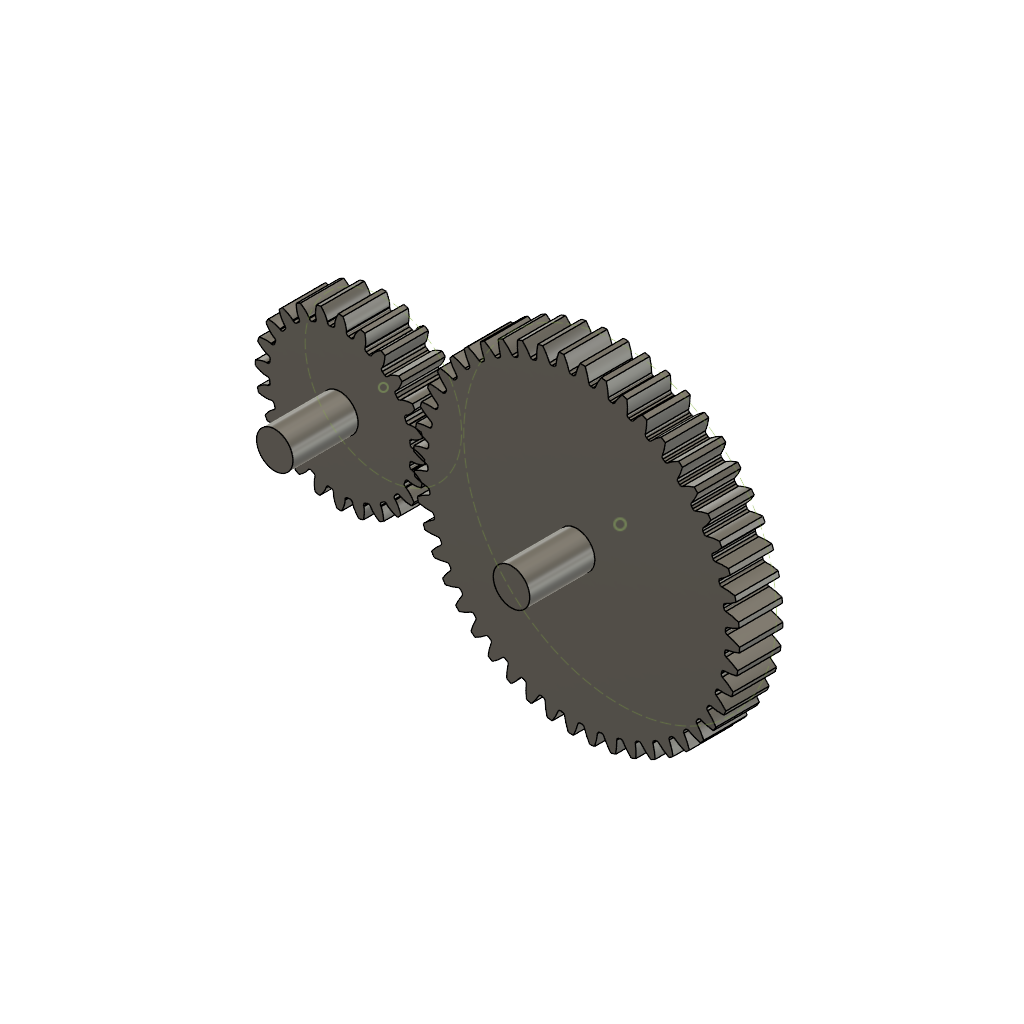
spur gear working (Autodesk Fusion 360 design; units mm, degrees)
part number: 2026-09-27-16-30-44-236
description: Spur Gear; Module: 1.5; Num Teeth: 24; Pressure Angle: 20.0; Backlash: 0.00 mm
part number: 2026-09-27-16-31-31-578
description: Spur Gear; Module: 1.5; Num Teeth: 48; Pressure Angle: 20.0; Backlash: 0.00 mm
part number: 2026-09-27-16-31-54-748
part number: 2026-09-27-16-35-08-701
part number: 2026-09-27-16-35-54-532
Autodesk Fusion 360 part; units mm, degrees
(part 1 of 7)
sketch "Base Circle" plane through (0, 0, 0) normal (0, 0, 1) x (1, 0, 0) in component "Spur Gear 24 teeth"
  circle A0 centre (0, 0) radius 16.2645
  circle A1 centre (0, 0) radius 4.2
extrude "Extrude1" add sketch "Base Circle" along normal blind 10 makes body 1 in component "Spur Gear 24 teeth"
sketch "Gear Tooth" plane through (0, 0, 0) normal (0, 0, 1) x (1, 0, 0) in component "Spur Gear 24 teeth"
  spline S0 degree 5 poles (16.8599, -1.3577) (16.8674, -1.3583) (16.8825, -1.3593) (16.9052, -1.3603) (16.9354, -1.3605) (16.9732, -1.3593) (17.0111, -1.357) (17.049, -1.3541) (17.0869, -1.3508) (17.1248, -1.3472) (17.1628, -1.3434) (17.2007, -1.3393) (17.2387, -1.3347) (17.2766, -1.3297) (17.3146, -1.3241) (17.3526, -1.318) (17.3906, -1.3115) (17.4285, -1.3047) (17.4665, -1.2975) (17.5045, -1.2901) (17.5425, -1.2824) (17.5804, -1.2744) (17.6184, -1.2661) (17.6563, -1.2574) (17.6943, -1.2485) (17.7322, -1.2392) (17.7701, -1.2297) (17.808, -1.2198) (17.8459, -1.2097) (17.8838, -1.1994) (17.9217, -1.1888) (17.9596, -1.1779) (17.9974, -1.1667) (18.0352, -1.1553) (18.0731, -1.1437) (18.1109, -1.1318) (18.1486, -1.1196) (18.1864, -1.1072) (18.2242, -1.0946) (18.2619, -1.0817) (18.2996, -1.0686) (18.3373, -1.0553) (18.3749, -1.0417) (18.4126, -1.0279) (18.4502, -1.0139) (18.4878, -0.9996) (18.5254, -0.9852) (18.563, -0.9705) (18.6005, -0.9556) (18.638, -0.9404) (18.6755, -0.9251) (18.7129, -0.9096) (18.7504, -0.8938) (18.7878, -0.8778) (18.8251, -0.8617) (18.8625, -0.8453) (18.8998, -0.8287) (18.9371, -0.8119) (18.9743, -0.7949) (19.0116, -0.7777) (19.0488, -0.7604) (19.0859, -0.7428) (19.1231, -0.725) (19.1602, -0.707) (19.1973, -0.6888) (19.2343, -0.6705) (19.2713, -0.6519) (19.3083, -0.6332) (19.3452, -0.6143) (19.3821, -0.5951) (19.419, -0.5758) (19.4485, -0.5602) (19.4705, -0.5484) (19.4853, -0.5406) (19.4926, -0.5366) knots 0 0 0 0 0 0 0.01428571 0.02857143 0.04285714 0.05714286 0.07142857 0.08571429 0.1 0.11428571 0.12857143 0.14285714 0.15714286 0.17142857 0.18571429 0.2 0.21428571 0.22857143 0.24285714 0.25714286 0.27142857 0.28571429 0.3 0.31428571 0.32857143 0.34285714 0.35714286 0.37142857 0.38571429 0.4 0.41428571 0.42857143 0.44285714 0.45714286 0.47142857 0.48571429 0.5 0.51428571 0.52857143 0.54285714 0.55714286 0.57142857 0.58571429 0.6 0.61428571 0.62857143 0.64285714 0.65714286 0.67142857 0.68571429 0.7 0.71428571 0.72857143 0.74285714 0.75714286 0.77142857 0.78571429 0.8 0.81428571 0.82857143 0.84285714 0.85714286 0.87142857 0.88571429 0.9 0.91428571 0.92857143 0.94285714 0.95714286 0.97142857 0.98571429 1 1 1 1 1 1
  spline S1 degree 5 poles (16.8599, 1.3577) (16.8674, 1.3583) (16.8825, 1.3593) (16.9052, 1.3603) (16.9354, 1.3605) (16.9732, 1.3593) (17.0111, 1.357) (17.049, 1.3541) (17.0869, 1.3508) (17.1248, 1.3472) (17.1628, 1.3434) (17.2007, 1.3393) (17.2387, 1.3347) (17.2766, 1.3297) (17.3146, 1.3241) (17.3526, 1.318) (17.3906, 1.3115) (17.4285, 1.3047) (17.4665, 1.2975) (17.5045, 1.2901) (17.5425, 1.2824) (17.5804, 1.2744) (17.6184, 1.2661) (17.6563, 1.2574) (17.6943, 1.2485) (17.7322, 1.2392) (17.7701, 1.2297) (17.808, 1.2198) (17.8459, 1.2097) (17.8838, 1.1994) (17.9217, 1.1888) (17.9596, 1.1779) (17.9974, 1.1667) (18.0352, 1.1553) (18.0731, 1.1437) (18.1109, 1.1318) (18.1486, 1.1196) (18.1864, 1.1072) (18.2242, 1.0946) (18.2619, 1.0817) (18.2996, 1.0686) (18.3373, 1.0553) (18.3749, 1.0417) (18.4126, 1.0279) (18.4502, 1.0139) (18.4878, 0.9996) (18.5254, 0.9852) (18.563, 0.9705) (18.6005, 0.9556) (18.638, 0.9404) (18.6755, 0.9251) (18.7129, 0.9096) (18.7504, 0.8938) (18.7878, 0.8778) (18.8251, 0.8617) (18.8625, 0.8453) (18.8998, 0.8287) (18.9371, 0.8119) (18.9743, 0.7949) (19.0116, 0.7777) (19.0488, 0.7604) (19.0859, 0.7428) (19.1231, 0.725) (19.1602, 0.707) (19.1973, 0.6888) (19.2343, 0.6705) (19.2713, 0.6519) (19.3083, 0.6332) (19.3452, 0.6143) (19.3821, 0.5951) (19.419, 0.5758) (19.4485, 0.5602) (19.4705, 0.5484) (19.4853, 0.5406) (19.4926, 0.5366) knots 0 0 0 0 0 0 0.01428571 0.02857143 0.04285714 0.05714286 0.07142857 0.08571429 0.1 0.11428571 0.12857143 0.14285714 0.15714286 0.17142857 0.18571429 0.2 0.21428571 0.22857143 0.24285714 0.25714286 0.27142857 0.28571429 0.3 0.31428571 0.32857143 0.34285714 0.35714286 0.37142857 0.38571429 0.4 0.41428571 0.42857143 0.44285714 0.45714286 0.47142857 0.48571429 0.5 0.51428571 0.52857143 0.54285714 0.55714286 0.57142857 0.58571429 0.6 0.61428571 0.62857143 0.64285714 0.65714286 0.67142857 0.68571429 0.7 0.71428571 0.72857143 0.74285714 0.75714286 0.77142857 0.78571429 0.8 0.81428571 0.82857143 0.84285714 0.85714286 0.87142857 0.88571429 0.9 0.91428571 0.92857143 0.94285714 0.95714286 0.97142857 0.98571429 1 1 1 1 1 1
  arc A0 (19.4926, -0.5366) -> (19.4926, 0.5366) centre (0, 0) ccw
  line L0 (16.2021, -1.3047) -> (16.8599, -1.3577)
  line L1 (16.2021, 1.3047) -> (16.8599, 1.3577)
  line L2 (16.2021, -1.3047) -> (16.2021, 1.3047)
  point P0 (17.0454, -1.3543)
  point P1 (17.2322, -1.3354)
  point P2 (17.4196, -1.3062)
  point P3 (17.6076, -1.2684)
  point P4 (17.7959, -1.2229)
  point P5 (17.9845, -1.1705)
  point P6 (18.1733, -1.1115)
  point P7 (18.3621, -1.0463)
  point P8 (18.551, -0.9751)
  point P9 (18.7398, -0.8982)
  point P10 (18.9284, -0.8158)
  point P11 (19.1168, -0.728)
  point P12 (19.3049, -0.6349)
  point P13 (17.0454, 1.3543)
  point P14 (17.2322, 1.3354)
  point P15 (17.4196, 1.3062)
  point P16 (17.6076, 1.2684)
  point P17 (17.7959, 1.2229)
  point P18 (17.9845, 1.1705)
  point P19 (18.1733, 1.1115)
  point P20 (18.3621, 1.0463)
  point P21 (18.551, 0.9751)
  point P22 (18.7398, 0.8982)
  point P23 (18.9284, 0.8158)
  point P24 (19.1168, 0.728)
  point P25 (19.3049, 0.6349)
extrude "Extrude2" add sketch "Gear Tooth" along normal blind 10 bodies 1 in component "Spur Gear 24 teeth"
fillet "Fillet1" radius 0.5 2 edges at (16.212, -1.3055, 5) (16.212, 1.3055, 5) on bodies 1 in component "Spur Gear 24 teeth"
pattern_circular "C-Pattern1" count 24 over 360 about axis through (0, 0, 0) along (0, 0, 1) of "Extrude2", "Fillet1" in component "Spur Gear 24 teeth"
sketch "Diametrial Pitch Circle" plane through (0, 0, 0) normal (0, 0, 1) x (1, 0, 0) in component "Spur Gear 24 teeth"
  circle A0 centre (0, 0) radius 18 construction
sketch "Base Circle (2)" plane through (0, 0, 0) normal (0, 0, 1) x (1, 0, 0) in component "Spur Gear 48 teeth"
  circle A0 centre (0, 0) radius 34.2645
  circle A1 centre (0, 0) radius 4.2
extrude "Extrude1'" add sketch "Base Circle (2)" along normal blind 10 separate body makes body 2 in component "Spur Gear 48 teeth"
sketch "Gear Tooth (2)" plane through (0, 0, 0) normal (0, 0, 1) x (1, 0, 0) in component "Spur Gear 48 teeth"
  spline S0 degree 5 poles (33.7906, -1.6106) (33.8012, -1.6107) (33.8226, -1.6107) (33.8546, -1.6104) (33.8974, -1.6095) (33.9508, -1.6076) (34.0042, -1.6048) (34.0576, -1.6012) (34.1111, -1.5968) (34.1645, -1.5917) (34.218, -1.5859) (34.2714, -1.5796) (34.3249, -1.5727) (34.3783, -1.5654) (34.4318, -1.5577) (34.4852, -1.5495) (34.5386, -1.541) (34.592, -1.532) (34.6454, -1.5226) (34.6988, -1.5128) (34.7521, -1.5026) (34.8055, -1.4921) (34.8588, -1.4812) (34.9121, -1.4699) (34.9654, -1.4583) (35.0187, -1.4464) (35.072, -1.4341) (35.1252, -1.4215) (35.1785, -1.4086) (35.2317, -1.3954) (35.2849, -1.3819) (35.338, -1.3681) (35.3912, -1.3539) (35.4443, -1.3395) (35.4974, -1.3248) (35.5505, -1.3098) (35.6036, -1.2945) (35.6566, -1.279) (35.7096, -1.2632) (35.7626, -1.2471) (35.8156, -1.2307) (35.8686, -1.2141) (35.9215, -1.1972) (35.9744, -1.18) (36.0272, -1.1626) (36.0801, -1.145) (36.1329, -1.1271) (36.1857, -1.1089) (36.2385, -1.0905) (36.2912, -1.0718) (36.3439, -1.0529) (36.3966, -1.0338) (36.4492, -1.0144) (36.5018, -0.9948) (36.5544, -0.975) (36.607, -0.9549) (36.6595, -0.9346) (36.712, -0.9141) (36.7645, -0.8933) (36.8169, -0.8723) (36.8693, -0.8511) (36.9217, -0.8297) (36.974, -0.808) (37.0263, -0.7862) (37.0786, -0.7641) (37.1308, -0.7418) (37.183, -0.7193) (37.2352, -0.6965) (37.2873, -0.6736) (37.3394, -0.6504) (37.3915, -0.6271) (37.4331, -0.6082) (37.4643, -0.594) (37.4851, -0.5844) (37.4955, -0.5797) knots 0 0 0 0 0 0 0.01428571 0.02857143 0.04285714 0.05714286 0.07142857 0.08571429 0.1 0.11428571 0.12857143 0.14285714 0.15714286 0.17142857 0.18571429 0.2 0.21428571 0.22857143 0.24285714 0.25714286 0.27142857 0.28571429 0.3 0.31428571 0.32857143 0.34285714 0.35714286 0.37142857 0.38571429 0.4 0.41428571 0.42857143 0.44285714 0.45714286 0.47142857 0.48571429 0.5 0.51428571 0.52857143 0.54285714 0.55714286 0.57142857 0.58571429 0.6 0.61428571 0.62857143 0.64285714 0.65714286 0.67142857 0.68571429 0.7 0.71428571 0.72857143 0.74285714 0.75714286 0.77142857 0.78571429 0.8 0.81428571 0.82857143 0.84285714 0.85714286 0.87142857 0.88571429 0.9 0.91428571 0.92857143 0.94285714 0.95714286 0.97142857 0.98571429 1 1 1 1 1 1
  spline S1 degree 5 poles (33.7906, 1.6106) (33.8012, 1.6107) (33.8226, 1.6107) (33.8546, 1.6104) (33.8974, 1.6095) (33.9508, 1.6076) (34.0042, 1.6048) (34.0576, 1.6012) (34.1111, 1.5968) (34.1645, 1.5917) (34.218, 1.5859) (34.2714, 1.5796) (34.3249, 1.5727) (34.3783, 1.5654) (34.4318, 1.5577) (34.4852, 1.5495) (34.5386, 1.541) (34.592, 1.532) (34.6454, 1.5226) (34.6988, 1.5128) (34.7521, 1.5026) (34.8055, 1.4921) (34.8588, 1.4812) (34.9121, 1.4699) (34.9654, 1.4583) (35.0187, 1.4464) (35.072, 1.4341) (35.1252, 1.4215) (35.1785, 1.4086) (35.2317, 1.3954) (35.2849, 1.3819) (35.338, 1.3681) (35.3912, 1.3539) (35.4443, 1.3395) (35.4974, 1.3248) (35.5505, 1.3098) (35.6036, 1.2945) (35.6566, 1.279) (35.7096, 1.2632) (35.7626, 1.2471) (35.8156, 1.2307) (35.8686, 1.2141) (35.9215, 1.1972) (35.9744, 1.18) (36.0272, 1.1626) (36.0801, 1.145) (36.1329, 1.1271) (36.1857, 1.1089) (36.2385, 1.0905) (36.2912, 1.0718) (36.3439, 1.0529) (36.3966, 1.0338) (36.4492, 1.0144) (36.5018, 0.9948) (36.5544, 0.975) (36.607, 0.9549) (36.6595, 0.9346) (36.712, 0.9141) (36.7645, 0.8933) (36.8169, 0.8723) (36.8693, 0.8511) (36.9217, 0.8297) (36.974, 0.808) (37.0263, 0.7862) (37.0786, 0.7641) (37.1308, 0.7418) (37.183, 0.7193) (37.2352, 0.6965) (37.2873, 0.6736) (37.3394, 0.6504) (37.3915, 0.6271) (37.4331, 0.6082) (37.4643, 0.594) (37.4851, 0.5844) (37.4955, 0.5797) knots 0 0 0 0 0 0 0.01428571 0.02857143 0.04285714 0.05714286 0.07142857 0.08571429 0.1 0.11428571 0.12857143 0.14285714 0.15714286 0.17142857 0.18571429 0.2 0.21428571 0.22857143 0.24285714 0.25714286 0.27142857 0.28571429 0.3 0.31428571 0.32857143 0.34285714 0.35714286 0.37142857 0.38571429 0.4 0.41428571 0.42857143 0.44285714 0.45714286 0.47142857 0.48571429 0.5 0.51428571 0.52857143 0.54285714 0.55714286 0.57142857 0.58571429 0.6 0.61428571 0.62857143 0.64285714 0.65714286 0.67142857 0.68571429 0.7 0.71428571 0.72857143 0.74285714 0.75714286 0.77142857 0.78571429 0.8 0.81428571 0.82857143 0.84285714 0.85714286 0.87142857 0.88571429 0.9 0.91428571 0.92857143 0.94285714 0.95714286 0.97142857 0.98571429 1 1 1 1 1 1
  arc A0 (37.4955, -0.5797) -> (37.4955, 0.5797) centre (0, 0) ccw
  line L0 (33.7906, 1.6106) -> (33.7906, -1.6106)
  point P0 (34.0535, -1.6013)
  point P1 (34.3173, -1.5736)
  point P2 (34.5816, -1.5337)
  point P3 (34.8462, -1.4837)
  point P4 (35.1111, -1.4248)
  point P5 (35.3762, -1.3579)
  point P6 (35.6414, -1.2834)
  point P7 (35.9066, -1.2019)
  point P8 (36.1718, -1.1136)
  point P9 (36.4369, -1.0189)
  point P10 (36.7019, -0.918)
  point P11 (36.9667, -0.811)
  point P12 (37.2312, -0.6982)
  point P13 (34.0535, 1.6013)
  point P14 (34.3173, 1.5736)
  point P15 (34.5816, 1.5337)
  point P16 (34.8462, 1.4837)
  point P17 (35.1111, 1.4248)
  point P18 (35.3762, 1.3579)
  point P19 (35.6414, 1.2834)
  point P20 (35.9066, 1.2019)
  point P21 (36.1718, 1.1136)
  point P22 (36.4369, 1.0189)
  point P23 (36.7019, 0.918)
  point P24 (36.9667, 0.811)
  point P25 (37.2312, 0.6982)
extrude "Extrude2'" add sketch "Gear Tooth (2)" along normal blind 10 bodies 2 in component "Spur Gear 48 teeth"
fillet "Fillet1'" radius 0.5 2 edges at (34.2278, 1.5846, 5) (34.2278, -1.5846, 5) on bodies 2 in component "Spur Gear 48 teeth"
pattern_circular "C-Pattern1'" count 48 over 360 about axis through (0, 0, 0) along (0, 0, 1) of "Extrude2'", "Fillet1'" in component "Spur Gear 48 teeth"
sketch "Diametrial Pitch Circle (2)" plane through (0, 0, 0) normal (0, 0, 1) x (1, 0, 0) in component "Spur Gear 48 teeth"
  circle A0 centre (0, 0) radius 36 construction
sketch "Sketch1" plane through (0, 0, 10) normal (0, 0, 1) x (1, 0, 0)
  arc A0 (88.7647, -0.2836) -> (88.7647, 0.2182) centre (54.5011, -0.0327) ccw
  spline S0 degree 3 poles (89.146, 0.7076) (89.0828, 0.6922) (89.0231, 0.6645) (88.9178, 0.5879) (88.8732, 0.5397) (88.8145, 0.4445) (88.7957, 0.4015) (88.7705, 0.3115) (88.7643, 0.2649) (88.7647, 0.2182) knots 0 0 0 0 0.019532 0.019532 0.039064 0.039064 0.053081 0.053081 0.067098 0.067098 0.067098 0.067098
  spline S1 degree 5 poles (89.146, 0.7076) (89.1512, 0.7089) (89.1669, 0.7127) (89.1931, 0.7192) (89.2298, 0.7285) (89.2771, 0.7408) (89.3296, 0.7548) (89.3821, 0.7692) (89.4346, 0.7839) (89.487, 0.799) (89.5394, 0.8144) (89.5918, 0.8301) (89.6441, 0.8461) (89.6963, 0.8625) (89.7486, 0.8791) (89.8008, 0.8961) (89.8529, 0.9134) (89.905, 0.931) (89.9571, 0.9488) (90.0091, 0.967) (90.0611, 0.9854) (90.1131, 1.0041) (90.165, 1.0231) (90.2169, 1.0424) (90.2687, 1.0619) (90.3205, 1.0817) (90.3722, 1.1017) (90.4239, 1.1221) (90.4756, 1.1426) (90.5272, 1.1635) (90.5788, 1.1845) (90.6303, 1.2059) (90.6818, 1.2274) (90.7333, 1.2493) (90.7847, 1.2713) (90.836, 1.2936) (90.8873, 1.3162) (90.9386, 1.3389) (90.9898, 1.3619) (91.041, 1.3852) (91.0921, 1.4086) (91.1432, 1.4323) (91.1943, 1.4563) (91.2452, 1.4804) (91.2962, 1.5048) (91.3471, 1.5294) (91.398, 1.5542) (91.4488, 1.5792) (91.4995, 1.6044) (91.5502, 1.6299) (91.6009, 1.6556) (91.6515, 1.6815) (91.7021, 1.7076) (91.7526, 1.7339) (91.8031, 1.7604) (91.8535, 1.7871) (91.8938, 1.8086) (91.924, 1.8249) (91.9442, 1.8357) (91.9542, 1.8412) knots 0.221564 0.221564 0.221564 0.221564 0.221564 0.221564 0.228571 0.242857 0.257143 0.271429 0.285714 0.3 0.314286 0.328571 0.342857 0.357143 0.371429 0.385714 0.4 0.414286 0.428571 0.442857 0.457143 0.471429 0.485714 0.5 0.514286 0.528571 0.542857 0.557143 0.571429 0.585714 0.6 0.614286 0.628571 0.642857 0.657143 0.671429 0.685714 0.7 0.714286 0.728571 0.742857 0.757143 0.771429 0.785714 0.8 0.814286 0.828571 0.842857 0.857143 0.871429 0.885714 0.9 0.914286 0.928571 0.942857 0.957143 0.971429 0.985714 1 1 1 1 1 1
  arc A1 (91.9542, 1.8412) -> (91.8784, 2.9981) centre (54.5011, -0.0327) ccw
  spline S2 degree 5 poles (91.8784, 2.9981) (91.8677, 3.0021) (91.8463, 3.0103) (91.8143, 3.0225) (91.7715, 3.0386) (91.718, 3.0585) (91.6645, 3.0782) (91.611, 3.0976) (91.5574, 3.1169) (91.5039, 3.136) (91.4503, 3.1548) (91.3967, 3.1734) (91.3431, 3.1918) (91.2894, 3.21) (91.2358, 3.228) (91.1821, 3.2457) (91.1284, 3.2632) (91.0747, 3.2805) (91.021, 3.2976) (90.9672, 3.3144) (90.9135, 3.331) (90.8597, 3.3473) (90.8059, 3.3635) (90.7521, 3.3793) (90.6983, 3.395) (90.6445, 3.4104) (90.5906, 3.4256) (90.5368, 3.4405) (90.4829, 3.4551) (90.429, 3.4696) (90.3751, 3.4837) (90.3212, 3.4976) (90.2673, 3.5113) (90.2134, 3.5247) (90.1595, 3.5378) (90.1056, 3.5507) (90.0516, 3.5633) (89.9977, 3.5756) (89.9438, 3.5877) (89.8898, 3.5994) (89.8359, 3.6109) (89.7819, 3.6221) (89.7279, 3.633) (89.674, 3.6436) (89.62, 3.654) (89.566, 3.664) (89.5121, 3.6737) (89.4581, 3.6831) (89.4042, 3.6922) (89.3502, 3.7009) (89.2963, 3.7093) (89.2423, 3.7174) (89.1884, 3.7252) (89.1344, 3.7326) (89.0805, 3.7396) (89.0321, 3.7456) (88.9945, 3.75) (88.9676, 3.7531) (88.9515, 3.7548) (88.9463, 3.7554) knots -1 -1 -1 -1 -1 -1 -0.985714 -0.971429 -0.957143 -0.942857 -0.928571 -0.914286 -0.9 -0.885714 -0.871429 -0.857143 -0.842857 -0.828571 -0.814286 -0.8 -0.785714 -0.771429 -0.757143 -0.742857 -0.728571 -0.714286 -0.7 -0.685714 -0.671429 -0.657143 -0.642857 -0.628571 -0.614286 -0.6 -0.585714 -0.571429 -0.557143 -0.542857 -0.528571 -0.514286 -0.5 -0.485714 -0.471429 -0.457143 -0.442857 -0.428571 -0.414286 -0.4 -0.385714 -0.371429 -0.357143 -0.342857 -0.328571 -0.314286 -0.3 -0.285714 -0.271429 -0.257143 -0.242857 -0.228571 -0.221564 -0.221564 -0.221564 -0.221564 -0.221564 -0.221564
  spline S3 degree 3 poles (88.5043, 4.1908) (88.5123, 4.1262) (88.5329, 4.0638) (88.5968, 3.9503) (88.6395, 3.9004) (88.7273, 3.8311) (88.7678, 3.8074) (88.8543, 3.772) (88.8998, 3.7605) (88.9463, 3.7554) knots 0 0 0 0 0.019532 0.019532 0.039064 0.039064 0.053081 0.053081 0.067098 0.067098 0.067098 0.067098
  arc A2 (88.5043, 4.1908) -> (88.4388, 4.6884) centre (54.5011, -0.0327) ccw
  spline S4 degree 3 poles (88.753, 5.2233) (88.6923, 5.1998) (88.6368, 5.1646) (88.5424, 5.0749) (88.5044, 5.0212) (88.4587, 4.9192) (88.4456, 4.8741) (88.4324, 4.7816) (88.4323, 4.7346) (88.4388, 4.6884) knots 0 0 0 0 0.019532 0.019532 0.039064 0.039064 0.053081 0.053081 0.067098 0.067098 0.067098 0.067098
  spline S5 degree 5 poles (88.753, 5.2233) (88.758, 5.2253) (88.773, 5.2311) (88.7982, 5.241) (88.8334, 5.255) (88.8786, 5.2733) (88.9289, 5.2941) (88.979, 5.3152) (89.0291, 5.3367) (89.0791, 5.3584) (89.1291, 5.3805) (89.1789, 5.4029) (89.2287, 5.4257) (89.2784, 5.4487) (89.328, 5.4721) (89.3775, 5.4957) (89.427, 5.5196) (89.4764, 5.5439) (89.5257, 5.5684) (89.5749, 5.5932) (89.624, 5.6182) (89.6731, 5.6435) (89.7221, 5.6691) (89.771, 5.695) (89.8198, 5.7211) (89.8686, 5.7475) (89.9173, 5.7742) (89.9659, 5.8011) (90.0144, 5.8282) (90.0629, 5.8556) (90.1113, 5.8832) (90.1596, 5.9111) (90.2078, 5.9392) (90.256, 5.9675) (90.304, 5.9961) (90.352, 6.0249) (90.4, 6.054) (90.4478, 6.0832) (90.4956, 6.1127) (90.5433, 6.1425) (90.5909, 6.1724) (90.6385, 6.2026) (90.686, 6.2329) (90.7334, 6.2635) (90.7807, 6.2943) (90.828, 6.3254) (90.8752, 6.3566) (90.9223, 6.3881) (90.9693, 6.4197) (91.0163, 6.4516) (91.0632, 6.4836) (91.11, 6.5159) (91.1567, 6.5484) (91.2034, 6.581) (91.2499, 6.6139) (91.2964, 6.647) (91.3336, 6.6736) (91.3614, 6.6937) (91.3799, 6.7071) (91.3892, 6.7138) knots 0.221564 0.221564 0.221564 0.221564 0.221564 0.221564 0.228571 0.242857 0.257143 0.271429 0.285714 0.3 0.314286 0.328571 0.342857 0.357143 0.371429 0.385714 0.4 0.414286 0.428571 0.442857 0.457143 0.471429 0.485714 0.5 0.514286 0.528571 0.542857 0.557143 0.571429 0.585714 0.6 0.614286 0.628571 0.642857 0.657143 0.671429 0.685714 0.7 0.714286 0.728571 0.742857 0.757143 0.771429 0.785714 0.8 0.814286 0.828571 0.842857 0.857143 0.871429 0.885714 0.9 0.914286 0.928571 0.942857 0.957143 0.971429 0.985714 1 1 1 1 1 1
  arc A3 (91.3892, 6.7138) -> (91.163, 7.8508) centre (54.5011, -0.0327) ccw
  spline S6 degree 5 poles (91.163, 7.8508) (91.1519, 7.8535) (91.1297, 7.8588) (91.0963, 7.8667) (91.0518, 7.877) (90.9961, 7.8898) (90.9405, 7.9023) (90.8849, 7.9147) (90.8293, 7.9268) (90.7737, 7.9387) (90.7181, 7.9504) (90.6626, 7.9618) (90.607, 7.9731) (90.5514, 7.9841) (90.4959, 7.9949) (90.4404, 8.0055) (90.3848, 8.0158) (90.3293, 8.026) (90.2738, 8.0359) (90.2184, 8.0455) (90.1629, 8.055) (90.1074, 8.0642) (90.052, 8.0731) (89.9966, 8.0819) (89.9412, 8.0903) (89.8858, 8.0986) (89.8305, 8.1066) (89.7751, 8.1144) (89.7198, 8.1219) (89.6645, 8.1291) (89.6092, 8.1361) (89.554, 8.1429) (89.4988, 8.1494) (89.4436, 8.1557) (89.3884, 8.1616) (89.3333, 8.1673) (89.2781, 8.1728) (89.223, 8.178) (89.168, 8.1829) (89.113, 8.1875) (89.058, 8.1919) (89.003, 8.1959) (88.9481, 8.1997) (88.8932, 8.2032) (88.8384, 8.2064) (88.7835, 8.2093) (88.7288, 8.2118) (88.6741, 8.2141) (88.6194, 8.2161) (88.5647, 8.2177) (88.5101, 8.219) (88.4556, 8.22) (88.4011, 8.2206) (88.3467, 8.2209) (88.2923, 8.2209) (88.2435, 8.2205) (88.2056, 8.22) (88.1786, 8.2195) (88.1624, 8.2191) (88.1571, 8.219) knots -1 -1 -1 -1 -1 -1 -0.985714 -0.971429 -0.957143 -0.942857 -0.928571 -0.914286 -0.9 -0.885714 -0.871429 -0.857143 -0.842857 -0.828571 -0.814286 -0.8 -0.785714 -0.771429 -0.757143 -0.742857 -0.728571 -0.714286 -0.7 -0.685714 -0.671429 -0.657143 -0.642857 -0.628571 -0.614286 -0.6 -0.585714 -0.571429 -0.557143 -0.542857 -0.528571 -0.514286 -0.5 -0.485714 -0.471429 -0.457143 -0.442857 -0.428571 -0.414286 -0.4 -0.385714 -0.371429 -0.357143 -0.342857 -0.328571 -0.314286 -0.3 -0.285714 -0.271429 -0.257143 -0.242857 -0.228571 -0.221564 -0.221564 -0.221564 -0.221564 -0.221564 -0.221564
  spline S7 degree 3 poles (87.6621, 8.593) (87.6785, 8.53) (87.707, 8.4708) (87.7852, 8.3666) (87.8341, 8.3227) (87.9301, 8.2654) (87.9734, 8.2473) (88.0638, 8.2235) (88.1104, 8.218) (88.1571, 8.219) knots 0 0 0 0 0.019532 0.019532 0.039064 0.039064 0.053081 0.053081 0.067098 0.067098 0.067098 0.067098
  arc A4 (87.6621, 8.593) -> (87.5322, 9.0777) centre (54.5011, -0.0327) ccw
  spline S8 degree 3 poles (87.7739, 9.6492) (87.7168, 9.6179) (87.6664, 9.5757) (87.5845, 9.4745) (87.5538, 9.4163) (87.5218, 9.3092) (87.5147, 9.2628) (87.5137, 9.1693) (87.5198, 9.1228) (87.5322, 9.0777) knots 0 0 0 0 0.019532 0.019532 0.039064 0.039064 0.053081 0.053081 0.067098 0.067098 0.067098 0.067098
  spline S9 degree 5 poles (87.7739, 9.6492) (87.7786, 9.6517) (87.7927, 9.6595) (87.8164, 9.6726) (87.8495, 9.691) (87.8919, 9.7151) (87.939, 9.7422) (87.986, 9.7697) (88.0329, 9.7975) (88.0796, 9.8257) (88.1263, 9.8541) (88.1728, 9.8828) (88.2191, 9.9118) (88.2654, 9.9412) (88.3115, 9.9708) (88.3576, 10.0007) (88.4035, 10.0309) (88.4493, 10.0613) (88.4949, 10.0921) (88.5405, 10.1231) (88.586, 10.1543) (88.6313, 10.1859) (88.6765, 10.2176) (88.7216, 10.2497) (88.7666, 10.2819) (88.8115, 10.3145) (88.8563, 10.3472) (88.901, 10.3802) (88.9456, 10.4135) (88.9901, 10.447) (89.0344, 10.4807) (89.0787, 10.5146) (89.1228, 10.5488) (89.1669, 10.5832) (89.2108, 10.6178) (89.2547, 10.6526) (89.2984, 10.6876) (89.342, 10.7229) (89.3855, 10.7584) (89.429, 10.7941) (89.4723, 10.83) (89.5155, 10.8661) (89.5586, 10.9024) (89.6016, 10.9389) (89.6445, 10.9757) (89.6873, 11.0126) (89.73, 11.0497) (89.7726, 11.087) (89.8151, 11.1246) (89.8575, 11.1623) (89.8998, 11.2002) (89.942, 11.2383) (89.9841, 11.2766) (90.0261, 11.3151) (90.068, 11.3537) (90.1098, 11.3926) (90.1431, 11.4238) (90.1681, 11.4474) (90.1847, 11.4631) (90.193, 11.4709) knots 0.221564 0.221564 0.221564 0.221564 0.221564 0.221564 0.228571 0.242857 0.257143 0.271429 0.285714 0.3 0.314286 0.328571 0.342857 0.357143 0.371429 0.385714 0.4 0.414286 0.428571 0.442857 0.457143 0.471429 0.485714 0.5 0.514286 0.528571 0.542857 0.557143 0.571429 0.585714 0.6 0.614286 0.628571 0.642857 0.657143 0.671429 0.685714 0.7 0.714286 0.728571 0.742857 0.757143 0.771429 0.785714 0.8 0.814286 0.828571 0.842857 0.857143 0.871429 0.885714 0.9 0.914286 0.928571 0.942857 0.957143 0.971429 0.985714 1 1 1 1 1 1
  arc A5 (90.193, 11.4709) -> (89.8204, 12.5687) centre (54.5011, -0.0327) ccw
  spline S10 degree 5 poles (89.8204, 12.5687) (89.809, 12.5699) (89.7862, 12.5723) (89.7521, 12.5757) (89.7066, 12.5802) (89.6498, 12.5856) (89.5931, 12.5908) (89.5363, 12.5957) (89.4796, 12.6005) (89.4229, 12.605) (89.3663, 12.6094) (89.3097, 12.6135) (89.2531, 12.6174) (89.1966, 12.621) (89.1401, 12.6245) (89.0837, 12.6277) (89.0273, 12.6308) (88.971, 12.6336) (88.9146, 12.6361) (88.8584, 12.6385) (88.8022, 12.6406) (88.746, 12.6425) (88.6898, 12.6441) (88.6338, 12.6455) (88.5777, 12.6467) (88.5218, 12.6477) (88.4658, 12.6484) (88.4099, 12.6488) (88.3541, 12.6491) (88.2984, 12.6491) (88.2426, 12.6488) (88.187, 12.6483) (88.1314, 12.6475) (88.0758, 12.6465) (88.0204, 12.6452) (87.9649, 12.6437) (87.9096, 12.6419) (87.8543, 12.6399) (87.7991, 12.6375) (87.7439, 12.6349) (87.6888, 12.6321) (87.6338, 12.6289) (87.5789, 12.6255) (87.524, 12.6218) (87.4692, 12.6178) (87.4145, 12.6135) (87.3598, 12.6089) (87.3053, 12.604) (87.2508, 12.5988) (87.1964, 12.5933) (87.1421, 12.5875) (87.0879, 12.5813) (87.0338, 12.5749) (86.9798, 12.5681) (86.9259, 12.5609) (86.8776, 12.5542) (86.8401, 12.5487) (86.8134, 12.5447) (86.7974, 12.5422) (86.7921, 12.5414) knots -1 -1 -1 -1 -1 -1 -0.985714 -0.971429 -0.957143 -0.942857 -0.928571 -0.914286 -0.9 -0.885714 -0.871429 -0.857143 -0.842857 -0.828571 -0.814286 -0.8 -0.785714 -0.771429 -0.757143 -0.742857 -0.728571 -0.714286 -0.7 -0.685714 -0.671429 -0.657143 -0.642857 -0.628571 -0.614286 -0.6 -0.585714 -0.571429 -0.557143 -0.542857 -0.528571 -0.514286 -0.5 -0.485714 -0.471429 -0.457143 -0.442857 -0.428571 -0.414286 -0.4 -0.385714 -0.371429 -0.357143 -0.342857 -0.328571 -0.314286 -0.3 -0.285714 -0.271429 -0.257143 -0.242857 -0.228571 -0.221564 -0.221564 -0.221564 -0.221564 -0.221564 -0.221564
  spline S11 degree 3 poles (86.2525, 12.8476) (86.277, 12.7873) (86.313, 12.7323) (86.4041, 12.6392) (86.4583, 12.6021) (86.561, 12.5578) (86.6063, 12.5455) (86.699, 12.5336) (86.746, 12.5343) (86.7921, 12.5414) knots 0 0 0 0 0.019532 0.019532 0.039064 0.039064 0.053081 0.053081 0.067098 0.067098 0.067098 0.067098
  arc A6 (86.2525, 12.8476) -> (86.0605, 13.3112) centre (54.5011, -0.0327) ccw
  spline S12 degree 3 poles (86.2255, 13.9093) (86.173, 13.8708) (86.1285, 13.8225) (86.0605, 13.7114) (86.0377, 13.6497) (86.0199, 13.5393) (86.019, 13.4924) (86.0302, 13.3996) (86.0423, 13.3543) (86.0605, 13.3112) knots 0 0 0 0 0.019532 0.019532 0.039064 0.039064 0.053081 0.053081 0.067098 0.067098 0.067098 0.067098
  spline S13 degree 5 poles (86.2255, 13.9093) (86.2298, 13.9124) (86.2428, 13.922) (86.2646, 13.938) (86.295, 13.9607) (86.3339, 13.9901) (86.3771, 14.0232) (86.4201, 14.0565) (86.4629, 14.0902) (86.5056, 14.1242) (86.5481, 14.1585) (86.5905, 14.193) (86.6327, 14.2279) (86.6747, 14.263) (86.7166, 14.2984) (86.7583, 14.334) (86.7999, 14.3699) (86.8413, 14.4061) (86.8826, 14.4426) (86.9237, 14.4792) (86.9647, 14.5162) (87.0055, 14.5533) (87.0462, 14.5907) (87.0868, 14.6284) (87.1272, 14.6662) (87.1674, 14.7044) (87.2076, 14.7427) (87.2476, 14.7812) (87.2874, 14.82) (87.3271, 14.859) (87.3667, 14.8982) (87.4062, 14.9376) (87.4455, 14.9773) (87.4847, 15.0171) (87.5237, 15.0572) (87.5626, 15.0974) (87.6014, 15.1379) (87.64, 15.1786) (87.6786, 15.2194) (87.717, 15.2605) (87.7552, 15.3017) (87.7933, 15.3432) (87.8314, 15.3848) (87.8692, 15.4266) (87.907, 15.4686) (87.9446, 15.5108) (87.9821, 15.5532) (88.0194, 15.5958) (88.0567, 15.6385) (88.0938, 15.6815) (88.1308, 15.7246) (88.1676, 15.7678) (88.2044, 15.8113) (88.241, 15.8549) (88.2775, 15.8987) (88.3138, 15.9427) (88.3428, 15.9781) (88.3645, 16.0046) (88.379, 16.0224) (88.3862, 16.0313) knots 0.221564 0.221564 0.221564 0.221564 0.221564 0.221564 0.228571 0.242857 0.257143 0.271429 0.285714 0.3 0.314286 0.328571 0.342857 0.357143 0.371429 0.385714 0.4 0.414286 0.428571 0.442857 0.457143 0.471429 0.485714 0.5 0.514286 0.528571 0.542857 0.557143 0.571429 0.585714 0.6 0.614286 0.628571 0.642857 0.657143 0.671429 0.685714 0.7 0.714286 0.728571 0.742857 0.757143 0.771429 0.785714 0.8 0.814286 0.828571 0.842857 0.857143 0.871429 0.885714 0.9 0.914286 0.928571 0.942857 0.957143 0.971429 0.985714 1 1 1 1 1 1
  arc A7 (88.3862, 16.0313) -> (87.8734, 17.071) centre (54.5011, -0.0327) ccw
  spline S14 degree 5 poles (87.8734, 17.071) (87.862, 17.0707) (87.8391, 17.0701) (87.8048, 17.069) (87.7591, 17.0675) (87.7021, 17.0655) (87.6451, 17.0632) (87.5882, 17.0607) (87.5314, 17.058) (87.4746, 17.0551) (87.4179, 17.052) (87.3612, 17.0487) (87.3047, 17.0452) (87.2481, 17.0415) (87.1917, 17.0375) (87.1353, 17.0334) (87.079, 17.029) (87.0228, 17.0244) (86.9666, 17.0196) (86.9105, 17.0146) (86.8545, 17.0093) (86.7986, 17.0039) (86.7427, 16.9982) (86.6869, 16.9923) (86.6312, 16.9861) (86.5756, 16.9798) (86.52, 16.9732) (86.4646, 16.9664) (86.4092, 16.9593) (86.3539, 16.952) (86.2987, 16.9445) (86.2436, 16.9367) (86.1886, 16.9287) (86.1336, 16.9204) (86.0788, 16.9119) (86.024, 16.9032) (85.9694, 16.8942) (85.9148, 16.8849) (85.8604, 16.8754) (85.806, 16.8656) (85.7518, 16.8556) (85.6977, 16.8453) (85.6436, 16.8347) (85.5897, 16.8239) (85.5359, 16.8128) (85.4822, 16.8014) (85.4287, 16.7897) (85.3752, 16.7777) (85.3219, 16.7655) (85.2687, 16.7529) (85.2156, 16.74) (85.1627, 16.7269) (85.1099, 16.7134) (85.0572, 16.6996) (85.0047, 16.6854) (84.9577, 16.6725) (84.9212, 16.6621) (84.8953, 16.6547) (84.8797, 16.6501) (84.8746, 16.6487) knots -1 -1 -1 -1 -1 -1 -0.985714 -0.971429 -0.957143 -0.942857 -0.928571 -0.914286 -0.9 -0.885714 -0.871429 -0.857143 -0.842857 -0.828571 -0.814286 -0.8 -0.785714 -0.771429 -0.757143 -0.742857 -0.728571 -0.714286 -0.7 -0.685714 -0.671429 -0.657143 -0.642857 -0.628571 -0.614286 -0.6 -0.585714 -0.571429 -0.557143 -0.542857 -0.528571 -0.514286 -0.5 -0.485714 -0.471429 -0.457143 -0.442857 -0.428571 -0.414286 -0.4 -0.385714 -0.371429 -0.357143 -0.342857 -0.328571 -0.314286 -0.3 -0.285714 -0.271429 -0.257143 -0.242857 -0.228571 -0.221564 -0.221564 -0.221564 -0.221564 -0.221564 -0.221564
  spline S15 degree 3 poles (84.2997, 16.8818) (84.3318, 16.8252) (84.3747, 16.7754) (84.4772, 16.695) (84.5357, 16.6652) (84.6433, 16.6348) (84.6899, 16.6284) (84.7833, 16.6288) (84.8298, 16.6356) (84.8746, 16.6487) knots 0 0 0 0 0.019532 0.019532 0.039064 0.039064 0.053081 0.053081 0.067098 0.067098 0.067098 0.067098
  arc A8 (84.2997, 16.8818) -> (84.0487, 17.3164) centre (54.5011, -0.0327) ccw
  spline S16 degree 3 poles (84.1343, 17.9309) (84.0873, 17.8859) (84.0495, 17.8321) (83.9966, 17.7131) (83.982, 17.6491) (83.9788, 17.5373) (83.984, 17.4906) (84.0072, 17.4001) (84.0251, 17.3567) (84.0487, 17.3164) knots 0 0 0 0 0.019532 0.019532 0.039064 0.039064 0.053081 0.053081 0.067098 0.067098 0.067098 0.067098
  spline S17 degree 5 poles (84.1343, 17.9309) (84.1382, 17.9346) (84.1498, 17.9458) (84.1693, 17.9645) (84.1965, 17.9909) (84.2312, 18.0251) (84.2697, 18.0636) (84.308, 18.1023) (84.3461, 18.1413) (84.384, 18.1805) (84.4216, 18.22) (84.4591, 18.2598) (84.4964, 18.2999) (84.5335, 18.3402) (84.5704, 18.3807) (84.6071, 18.4215) (84.6436, 18.4626) (84.68, 18.5038) (84.7161, 18.5453) (84.7521, 18.5871) (84.7879, 18.629) (84.8236, 18.6712) (84.859, 18.7136) (84.8943, 18.7562) (84.9295, 18.7991) (84.9644, 18.8421) (84.9992, 18.8853) (85.0338, 18.9288) (85.0683, 18.9724) (85.1025, 19.0163) (85.1367, 19.0603) (85.1706, 19.1046) (85.2044, 19.149) (85.2381, 19.1936) (85.2716, 19.2384) (85.3049, 19.2834) (85.3381, 19.3286) (85.3711, 19.3739) (85.4039, 19.4195) (85.4366, 19.4652) (85.4692, 19.5111) (85.5016, 19.5571) (85.5338, 19.6034) (85.5659, 19.6498) (85.5978, 19.6964) (85.6296, 19.7431) (85.6613, 19.79) (85.6928, 19.8371) (85.7241, 19.8843) (85.7553, 19.9317) (85.7863, 19.9793) (85.8172, 20.027) (85.848, 20.0749) (85.8786, 20.123) (85.909, 20.1712) (85.9394, 20.2195) (85.9635, 20.2583) (85.9815, 20.2875) (85.9935, 20.307) (85.9995, 20.3167) knots 0.221564 0.221564 0.221564 0.221564 0.221564 0.221564 0.228571 0.242857 0.257143 0.271429 0.285714 0.3 0.314286 0.328571 0.342857 0.357143 0.371429 0.385714 0.4 0.414286 0.428571 0.442857 0.457143 0.471429 0.485714 0.5 0.514286 0.528571 0.542857 0.557143 0.571429 0.585714 0.6 0.614286 0.628571 0.642857 0.657143 0.671429 0.685714 0.7 0.714286 0.728571 0.742857 0.757143 0.771429 0.785714 0.8 0.814286 0.828571 0.842857 0.857143 0.871429 0.885714 0.9 0.914286 0.928571 0.942857 0.957143 0.971429 0.985714 1 1 1 1 1 1
  arc A9 (85.9995, 20.3167) -> (85.3554, 21.2807) centre (54.5011, -0.0327) ccw
  spline S18 degree 5 poles (85.3554, 21.2807) (85.3441, 21.2789) (85.3215, 21.2752) (85.2877, 21.2697) (85.2426, 21.2623) (85.1863, 21.2528) (85.1301, 21.2431) (85.074, 21.2332) (85.018, 21.2231) (84.9621, 21.2129) (84.9063, 21.2024) (84.8506, 21.1917) (84.7949, 21.1808) (84.7394, 21.1697) (84.6839, 21.1585) (84.6286, 21.147) (84.5733, 21.1353) (84.5182, 21.1234) (84.4631, 21.1113) (84.4081, 21.099) (84.3533, 21.0865) (84.2985, 21.0738) (84.2439, 21.0609) (84.1894, 21.0477) (84.1349, 21.0344) (84.0806, 21.0208) (84.0264, 21.007) (83.9723, 20.993) (83.9183, 20.9788) (83.8645, 20.9643) (83.8107, 20.9496) (83.7571, 20.9347) (83.7036, 20.9196) (83.6502, 20.9043) (83.5969, 20.8887) (83.5438, 20.8729) (83.4908, 20.8568) (83.4379, 20.8405) (83.3852, 20.824) (83.3326, 20.8072) (83.2801, 20.7902) (83.2278, 20.7729) (83.1756, 20.7553) (83.1235, 20.7376) (83.0716, 20.7195) (83.0199, 20.7012) (82.9683, 20.6826) (82.9169, 20.6638) (82.8656, 20.6447) (82.8145, 20.6253) (82.7636, 20.6056) (82.7128, 20.5856) (82.6622, 20.5654) (82.6118, 20.5448) (82.5616, 20.5239) (82.5167, 20.5049) (82.4819, 20.4899) (82.4571, 20.4791) (82.4423, 20.4726) (82.4374, 20.4705) knots -1 -1 -1 -1 -1 -1 -0.985714 -0.971429 -0.957143 -0.942857 -0.928571 -0.914286 -0.9 -0.885714 -0.871429 -0.857143 -0.842857 -0.828571 -0.814286 -0.8 -0.785714 -0.771429 -0.757143 -0.742857 -0.728571 -0.714286 -0.7 -0.685714 -0.671429 -0.657143 -0.642857 -0.628571 -0.614286 -0.6 -0.585714 -0.571429 -0.557143 -0.542857 -0.528571 -0.514286 -0.5 -0.485714 -0.471429 -0.457143 -0.442857 -0.428571 -0.414286 -0.4 -0.385714 -0.371429 -0.357143 -0.342857 -0.328571 -0.314286 -0.3 -0.285714 -0.271429 -0.257143 -0.242857 -0.228571 -0.221564 -0.221564 -0.221564 -0.221564 -0.221564 -0.221564
  spline S19 degree 3 poles (81.8369, 20.6266) (81.8762, 20.5746) (81.9252, 20.5309) (82.0373, 20.4646) (82.0993, 20.4427) (82.2099, 20.4265) (82.2569, 20.4263) (82.3495, 20.4389) (82.3947, 20.4516) (82.4374, 20.4705) knots 0 0 0 0 0.019532 0.019532 0.039064 0.039064 0.053081 0.053081 0.067098 0.067098 0.067098 0.067098
  arc A10 (81.8369, 20.6266) -> (81.5314, 21.0247) centre (54.5011, -0.0327) ccw
  spline S20 degree 3 poles (81.5361, 21.6451) (81.4953, 21.5944) (81.4648, 21.5361) (81.4279, 21.4113) (81.4219, 21.3458) (81.4332, 21.2346) (81.4445, 21.189) (81.4793, 21.1023) (81.5027, 21.0616) (81.5314, 21.0247) knots 0 0 0 0 0.019532 0.019532 0.039064 0.039064 0.053081 0.053081 0.067098 0.067098 0.067098 0.067098
  spline S21 degree 5 poles (81.5361, 21.6451) (81.5394, 21.6493) (81.5495, 21.6619) (81.5664, 21.683) (81.5899, 21.7127) (81.6199, 21.7512) (81.653, 21.7943) (81.6859, 21.8377) (81.7186, 21.8813) (81.751, 21.9252) (81.7832, 21.9693) (81.8152, 22.0136) (81.8469, 22.0582) (81.8784, 22.103) (81.9097, 22.148) (81.9408, 22.1933) (81.9716, 22.2387) (82.0023, 22.2844) (82.0327, 22.3303) (82.063, 22.3763) (82.093, 22.4226) (82.1228, 22.4691) (82.1524, 22.5158) (82.1819, 22.5626) (82.2111, 22.6097) (82.2401, 22.6569) (82.269, 22.7043) (82.2976, 22.7519) (82.3261, 22.7997) (82.3544, 22.8476) (82.3824, 22.8957) (82.4103, 22.944) (82.4381, 22.9925) (82.4656, 23.0411) (82.4929, 23.0899) (82.5201, 23.1388) (82.5471, 23.188) (82.5739, 23.2372) (82.6005, 23.2867) (82.627, 23.3363) (82.6533, 23.386) (82.6794, 23.4359) (82.7053, 23.486) (82.7311, 23.5362) (82.7567, 23.5865) (82.7821, 23.637) (82.8073, 23.6877) (82.8324, 23.7384) (82.8573, 23.7894) (82.882, 23.8404) (82.9066, 23.8917) (82.931, 23.943) (82.9552, 23.9945) (82.9793, 24.0461) (83.0032, 24.0979) (83.027, 24.1498) (83.0458, 24.1914) (83.0599, 24.2227) (83.0692, 24.2435) (83.0739, 24.254) knots 0.221564 0.221564 0.221564 0.221564 0.221564 0.221564 0.228571 0.242857 0.257143 0.271429 0.285714 0.3 0.314286 0.328571 0.342857 0.357143 0.371429 0.385714 0.4 0.414286 0.428571 0.442857 0.457143 0.471429 0.485714 0.5 0.514286 0.528571 0.542857 0.557143 0.571429 0.585714 0.6 0.614286 0.628571 0.642857 0.657143 0.671429 0.685714 0.7 0.714286 0.728571 0.742857 0.757143 0.771429 0.785714 0.8 0.814286 0.828571 0.842857 0.857143 0.871429 0.885714 0.9 0.914286 0.928571 0.942857 0.957143 0.971429 0.985714 1 1 1 1 1 1
  arc A11 (83.0739, 24.254) -> (82.3095, 25.1256) centre (54.5011, -0.0327) ccw
  spline S22 degree 5 poles (82.3095, 25.1256) (82.2985, 25.1224) (82.2766, 25.1158) (82.2438, 25.106) (82.2, 25.0927) (82.1455, 25.0759) (82.091, 25.059) (82.0367, 25.0419) (81.9825, 25.0245) (81.9284, 25.0071) (81.8744, 24.9894) (81.8206, 24.9715) (81.7668, 24.9535) (81.7132, 24.9352) (81.6597, 24.9168) (81.6063, 24.8982) (81.5531, 24.8794) (81.4999, 24.8604) (81.4469, 24.8413) (81.394, 24.8219) (81.3413, 24.8023) (81.2887, 24.7826) (81.2362, 24.7626) (81.1838, 24.7425) (81.1316, 24.7221) (81.0795, 24.7016) (81.0276, 24.6808) (80.9758, 24.6599) (80.9241, 24.6387) (80.8726, 24.6174) (80.8212, 24.5958) (80.77, 24.574) (80.7189, 24.5521) (80.668, 24.5299) (80.6172, 24.5075) (80.5666, 24.4848) (80.5161, 24.462) (80.4658, 24.4389) (80.4157, 24.4157) (80.3657, 24.3922) (80.3159, 24.3684) (80.2663, 24.3445) (80.2169, 24.3203) (80.1676, 24.2958) (80.1185, 24.2712) (80.0696, 24.2463) (80.0209, 24.2211) (79.9723, 24.1957) (79.924, 24.1701) (79.8759, 24.1442) (79.8279, 24.118) (79.7802, 24.0916) (79.7327, 24.0649) (79.6854, 24.0379) (79.6383, 24.0107) (79.5963, 23.986) (79.5637, 23.9666) (79.5406, 23.9526) (79.5268, 23.9443) (79.5222, 23.9415) knots -1 -1 -1 -1 -1 -1 -0.985714 -0.971429 -0.957143 -0.942857 -0.928571 -0.914286 -0.9 -0.885714 -0.871429 -0.857143 -0.842857 -0.828571 -0.814286 -0.8 -0.785714 -0.771429 -0.757143 -0.742857 -0.728571 -0.714286 -0.7 -0.685714 -0.671429 -0.657143 -0.642857 -0.628571 -0.614286 -0.6 -0.585714 -0.571429 -0.557143 -0.542857 -0.528571 -0.514286 -0.5 -0.485714 -0.471429 -0.457143 -0.442857 -0.428571 -0.414286 -0.4 -0.385714 -0.371429 -0.357143 -0.342857 -0.328571 -0.314286 -0.3 -0.285714 -0.271429 -0.257143 -0.242857 -0.228571 -0.221564 -0.221564 -0.221564 -0.221564 -0.221564 -0.221564
  spline S23 degree 3 poles (78.9065, 24.0179) (78.9522, 23.9715) (79.0065, 23.9345) (79.1263, 23.8834) (79.1906, 23.8698) (79.3024, 23.8682) (79.349, 23.8741) (79.4392, 23.8987) (79.4823, 23.9172) (79.5222, 23.9415) knots 0 0 0 0 0.019532 0.019532 0.039064 0.039064 0.053081 0.053081 0.067098 0.067098 0.067098 0.067098
  arc A12 (78.9065, 24.0179) -> (78.5517, 24.3727) centre (54.5011, -0.0327) ccw
  spline S24 degree 3 poles (78.4753, 24.9885) (78.4415, 24.9328) (78.4189, 24.8711) (78.3986, 24.7425) (78.4011, 24.6768) (78.4269, 24.568) (78.444, 24.5243) (78.4899, 24.4428) (78.5184, 24.4055) (78.5517, 24.3727) knots 0 0 0 0 0.019532 0.019532 0.039064 0.039064 0.053081 0.053081 0.067098 0.067098 0.067098 0.067098
  spline S25 degree 5 poles (78.4753, 24.9885) (78.478, 24.993) (78.4864, 25.0068) (78.5004, 25.03) (78.5198, 25.0625) (78.5445, 25.1046) (78.5717, 25.1516) (78.5987, 25.1989) (78.6254, 25.2464) (78.6518, 25.2942) (78.678, 25.3421) (78.7039, 25.3902) (78.7295, 25.4386) (78.7549, 25.4871) (78.7801, 25.5358) (78.805, 25.5847) (78.8296, 25.6338) (78.854, 25.6831) (78.8782, 25.7326) (78.9022, 25.7822) (78.9259, 25.832) (78.9494, 25.8819) (78.9727, 25.9321) (78.9958, 25.9824) (79.0186, 26.0328) (79.0412, 26.0834) (79.0636, 26.1342) (79.0858, 26.1851) (79.1078, 26.2362) (79.1296, 26.2874) (79.1512, 26.3388) (79.1725, 26.3903) (79.1937, 26.442) (79.2146, 26.4938) (79.2354, 26.5457) (79.2559, 26.5978) (79.2763, 26.65) (79.2964, 26.7024) (79.3164, 26.7549) (79.3361, 26.8075) (79.3557, 26.8603) (79.375, 26.9131) (79.3942, 26.9661) (79.4132, 27.0193) (79.432, 27.0725) (79.4506, 27.1259) (79.469, 27.1794) (79.4873, 27.2331) (79.5053, 27.2868) (79.5232, 27.3407) (79.5408, 27.3946) (79.5583, 27.4487) (79.5756, 27.5029) (79.5928, 27.5573) (79.6097, 27.6117) (79.6265, 27.6663) (79.6397, 27.71) (79.6496, 27.7428) (79.6561, 27.7648) (79.6594, 27.7757) knots 0.221564 0.221564 0.221564 0.221564 0.221564 0.221564 0.228571 0.242857 0.257143 0.271429 0.285714 0.3 0.314286 0.328571 0.342857 0.357143 0.371429 0.385714 0.4 0.414286 0.428571 0.442857 0.457143 0.471429 0.485714 0.5 0.514286 0.528571 0.542857 0.557143 0.571429 0.585714 0.6 0.614286 0.628571 0.642857 0.657143 0.671429 0.685714 0.7 0.714286 0.728571 0.742857 0.757143 0.771429 0.785714 0.8 0.814286 0.828571 0.842857 0.857143 0.871429 0.885714 0.9 0.914286 0.928571 0.942857 0.957143 0.971429 0.985714 1 1 1 1 1 1
  arc A13 (79.6594, 27.7757) -> (78.7878, 28.5401) centre (54.5011, -0.0327) ccw
  spline S26 degree 5 poles (78.7878, 28.5401) (78.7773, 28.5355) (78.7564, 28.5261) (78.7252, 28.512) (78.6835, 28.4932) (78.6316, 28.4694) (78.5799, 28.4455) (78.5283, 28.4215) (78.4768, 28.3972) (78.4254, 28.3728) (78.3742, 28.3483) (78.3231, 28.3235) (78.2722, 28.2986) (78.2214, 28.2735) (78.1708, 28.2483) (78.1203, 28.2229) (78.0699, 28.1973) (78.0197, 28.1715) (77.9697, 28.1456) (77.9198, 28.1195) (77.87, 28.0932) (77.8204, 28.0668) (77.771, 28.0401) (77.7217, 28.0133) (77.6726, 27.9863) (77.6237, 27.9592) (77.5749, 27.9318) (77.5262, 27.9043) (77.4778, 27.8766) (77.4295, 27.8487) (77.3814, 27.8206) (77.3334, 27.7923) (77.2857, 27.7639) (77.2381, 27.7352) (77.1907, 27.7064) (77.1434, 27.6773) (77.0964, 27.6481) (77.0495, 27.6187) (77.0029, 27.589) (76.9564, 27.5592) (76.9101, 27.5292) (76.864, 27.499) (76.8182, 27.4685) (76.7725, 27.4379) (76.727, 27.407) (76.6818, 27.3759) (76.6368, 27.3446) (76.592, 27.3131) (76.5474, 27.2814) (76.5031, 27.2494) (76.459, 27.2172) (76.4151, 27.1848) (76.3715, 27.1521) (76.3281, 27.1192) (76.285, 27.0861) (76.2465, 27.0561) (76.2168, 27.0326) (76.1957, 27.0158) (76.183, 27.0056) (76.1789, 27.0023) knots -1 -1 -1 -1 -1 -1 -0.985714 -0.971429 -0.957143 -0.942857 -0.928571 -0.914286 -0.9 -0.885714 -0.871429 -0.857143 -0.842857 -0.828571 -0.814286 -0.8 -0.785714 -0.771429 -0.757143 -0.742857 -0.728571 -0.714286 -0.7 -0.685714 -0.671429 -0.657143 -0.642857 -0.628571 -0.614286 -0.6 -0.585714 -0.571429 -0.557143 -0.542857 -0.528571 -0.514286 -0.5 -0.485714 -0.471429 -0.457143 -0.442857 -0.428571 -0.414286 -0.4 -0.385714 -0.371429 -0.357143 -0.342857 -0.328571 -0.314286 -0.3 -0.285714 -0.271429 -0.257143 -0.242857 -0.228571 -0.221564 -0.221564 -0.221564 -0.221564 -0.221564 -0.221564
  spline S27 degree 3 poles (75.5585, 26.9977) (75.6098, 26.9577) (75.6685, 26.9281) (75.7939, 26.893) (75.8595, 26.8879) (75.9705, 26.901) (76.0159, 26.9129) (76.1021, 26.949) (76.1425, 26.9731) (76.1789, 27.0023) knots 0 0 0 0 0.019532 0.019532 0.039064 0.039064 0.053081 0.053081 0.067098 0.067098 0.067098 0.067098
  arc A14 (75.5585, 26.9977) -> (75.1604, 27.3032) centre (54.5011, -0.0327) ccw
  spline S28 degree 3 poles (75.0043, 27.9037) (74.978, 27.8441) (74.9636, 27.7799) (74.9603, 27.6498) (74.9714, 27.585) (75.0112, 27.4805) (75.0338, 27.4393) (75.0899, 27.3646) (75.1231, 27.3313) (75.1604, 27.3032) knots 0 0 0 0 0.019532 0.019532 0.039064 0.039064 0.053081 0.053081 0.067098 0.067098 0.067098 0.067098
  spline S29 degree 5 poles (75.0043, 27.9037) (75.0064, 27.9085) (75.0129, 27.9233) (75.0237, 27.9481) (75.0387, 27.9829) (75.0577, 28.0278) (75.0786, 28.078) (75.0991, 28.1284) (75.1194, 28.179) (75.1394, 28.2298) (75.159, 28.2807) (75.1784, 28.3318) (75.1976, 28.3831) (75.2164, 28.4345) (75.235, 28.4861) (75.2533, 28.5379) (75.2713, 28.5898) (75.2891, 28.6418) (75.3066, 28.694) (75.3239, 28.7463) (75.341, 28.7988) (75.3577, 28.8514) (75.3743, 28.9041) (75.3906, 28.957) (75.4066, 29.01) (75.4224, 29.0631) (75.438, 29.1164) (75.4534, 29.1698) (75.4685, 29.2233) (75.4834, 29.2769) (75.4981, 29.3307) (75.5125, 29.3846) (75.5268, 29.4385) (75.5408, 29.4926) (75.5546, 29.5468) (75.5681, 29.6012) (75.5815, 29.6556) (75.5946, 29.7101) (75.6076, 29.7648) (75.6203, 29.8195) (75.6328, 29.8744) (75.6451, 29.9293) (75.6572, 29.9844) (75.6691, 30.0395) (75.6808, 30.0948) (75.6922, 30.1501) (75.7035, 30.2056) (75.7146, 30.2611) (75.7255, 30.3168) (75.7361, 30.3725) (75.7466, 30.4283) (75.7569, 30.4843) (75.767, 30.5403) (75.7769, 30.5964) (75.7866, 30.6525) (75.7961, 30.7088) (75.8035, 30.7539) (75.809, 30.7878) (75.8126, 30.8103) (75.8144, 30.8216) knots 0.221564 0.221564 0.221564 0.221564 0.221564 0.221564 0.228571 0.242857 0.257143 0.271429 0.285714 0.3 0.314286 0.328571 0.342857 0.357143 0.371429 0.385714 0.4 0.414286 0.428571 0.442857 0.457143 0.471429 0.485714 0.5 0.514286 0.528571 0.542857 0.557143 0.571429 0.585714 0.6 0.614286 0.628571 0.642857 0.657143 0.671429 0.685714 0.7 0.714286 0.728571 0.742857 0.757143 0.771429 0.785714 0.8 0.814286 0.828571 0.842857 0.857143 0.871429 0.885714 0.9 0.914286 0.928571 0.942857 0.957143 0.971429 0.985714 1 1 1 1 1 1
  arc A15 (75.8144, 30.8216) -> (74.8505, 31.4657) centre (54.5011, -0.0327) ccw
  spline S30 degree 5 poles (74.8505, 31.4657) (74.8407, 31.4597) (74.8213, 31.4477) (74.7921, 31.4297) (74.7533, 31.4056) (74.7049, 31.3753) (74.6567, 31.3448) (74.6087, 31.3142) (74.5608, 31.2835) (74.5131, 31.2526) (74.4655, 31.2215) (74.4181, 31.1903) (74.3709, 31.159) (74.3238, 31.1275) (74.2769, 31.0959) (74.2301, 31.0641) (74.1835, 31.0321) (74.1371, 31) (74.0909, 30.9678) (74.0448, 30.9354) (73.9989, 30.9029) (73.9532, 30.8702) (73.9077, 30.8373) (73.8623, 30.8043) (73.8172, 30.7711) (73.7722, 30.7378) (73.7274, 30.7043) (73.6828, 30.6707) (73.6383, 30.6369) (73.5941, 30.6029) (73.55, 30.5688) (73.5062, 30.5345) (73.4626, 30.5) (73.4191, 30.4654) (73.3759, 30.4306) (73.3328, 30.3957) (73.29, 30.3606) (73.2474, 30.3253) (73.205, 30.2898) (73.1628, 30.2542) (73.1209, 30.2184) (73.0791, 30.1824) (73.0376, 30.1462) (72.9963, 30.1099) (72.9553, 30.0733) (72.9145, 30.0366) (72.8739, 29.9997) (72.8336, 29.9626) (72.7936, 29.9253) (72.7538, 29.8879) (72.7143, 29.8502) (72.675, 29.8123) (72.636, 29.7742) (72.5973, 29.7359) (72.5589, 29.6975) (72.5247, 29.6627) (72.4983, 29.6355) (72.4795, 29.6161) (72.4683, 29.6044) (72.4647, 29.6006) knots -1 -1 -1 -1 -1 -1 -0.985714 -0.971429 -0.957143 -0.942857 -0.928571 -0.914286 -0.9 -0.885714 -0.871429 -0.857143 -0.842857 -0.828571 -0.814286 -0.8 -0.785714 -0.771429 -0.757143 -0.742857 -0.728571 -0.714286 -0.7 -0.685714 -0.671429 -0.657143 -0.642857 -0.628571 -0.614286 -0.6 -0.585714 -0.571429 -0.557143 -0.542857 -0.528571 -0.514286 -0.5 -0.485714 -0.471429 -0.457143 -0.442857 -0.428571 -0.414286 -0.4 -0.385714 -0.371429 -0.357143 -0.342857 -0.328571 -0.314286 -0.3 -0.285714 -0.271429 -0.257143 -0.242857 -0.228571 -0.221564 -0.221564 -0.221564 -0.221564 -0.221564 -0.221564
  spline S31 degree 3 poles (71.8502, 29.515) (71.9063, 29.482) (71.9684, 29.4603) (72.0973, 29.442) (72.1629, 29.4455) (72.2713, 29.4729) (72.3148, 29.4907) (72.3955, 29.5377) (72.4324, 29.5668) (72.4647, 29.6006) knots 0 0 0 0 0.019532 0.019532 0.039064 0.039064 0.053081 0.053081 0.067098 0.067098 0.067098 0.067098
  arc A16 (71.8502, 29.515) -> (71.4156, 29.7659) centre (54.5011, -0.0327) ccw
  spline S32 degree 3 poles (71.1824, 30.3409) (71.1642, 30.2784) (71.1583, 30.2129) (71.172, 30.0834) (71.1914, 30.0206) (71.2445, 29.9222) (71.2724, 29.8844) (71.3377, 29.8176) (71.3749, 29.789) (71.4156, 29.7659) knots 0 0 0 0 0.019532 0.019532 0.039064 0.039064 0.053081 0.053081 0.067098 0.067098 0.067098 0.067098
  spline S33 degree 5 poles (71.1824, 30.3409) (71.1839, 30.346) (71.1884, 30.3615) (71.1959, 30.3874) (71.2062, 30.4239) (71.2192, 30.4709) (71.2333, 30.5234) (71.2471, 30.5761) (71.2606, 30.6289) (71.2738, 30.6818) (71.2867, 30.7349) (71.2992, 30.7881) (71.3115, 30.8414) (71.3235, 30.8949) (71.3352, 30.9484) (71.3465, 31.0021) (71.3577, 31.0559) (71.3685, 31.1099) (71.3791, 31.1639) (71.3894, 31.218) (71.3994, 31.2723) (71.4092, 31.3266) (71.4187, 31.3811) (71.4279, 31.4356) (71.4369, 31.4903) (71.4457, 31.545) (71.4542, 31.5999) (71.4625, 31.6548) (71.4705, 31.7098) (71.4782, 31.7649) (71.4858, 31.8201) (71.4931, 31.8754) (71.5001, 31.9308) (71.507, 31.9863) (71.5135, 32.0418) (71.5199, 32.0974) (71.5261, 32.1531) (71.532, 32.2089) (71.5377, 32.2648) (71.5431, 32.3207) (71.5484, 32.3768) (71.5534, 32.4328) (71.5582, 32.489) (71.5628, 32.5452) (71.5671, 32.6016) (71.5713, 32.6579) (71.5752, 32.7144) (71.579, 32.7709) (71.5825, 32.8275) (71.5858, 32.8841) (71.5889, 32.9408) (71.5918, 32.9976) (71.5945, 33.0545) (71.597, 33.1114) (71.5992, 33.1683) (71.6013, 33.2254) (71.6028, 33.271) (71.6038, 33.3053) (71.6045, 33.3282) (71.6048, 33.3396) knots 0.221564 0.221564 0.221564 0.221564 0.221564 0.221564 0.228571 0.242857 0.257143 0.271429 0.285714 0.3 0.314286 0.328571 0.342857 0.357143 0.371429 0.385714 0.4 0.414286 0.428571 0.442857 0.457143 0.471429 0.485714 0.5 0.514286 0.528571 0.542857 0.557143 0.571429 0.585714 0.6 0.614286 0.628571 0.642857 0.657143 0.671429 0.685714 0.7 0.714286 0.728571 0.742857 0.757143 0.771429 0.785714 0.8 0.814286 0.828571 0.842857 0.857143 0.871429 0.885714 0.9 0.914286 0.928571 0.942857 0.957143 0.971429 0.985714 1 1 1 1 1 1
  arc A17 (71.6048, 33.3396) -> (70.565, 33.8524) centre (54.5011, -0.0327) ccw